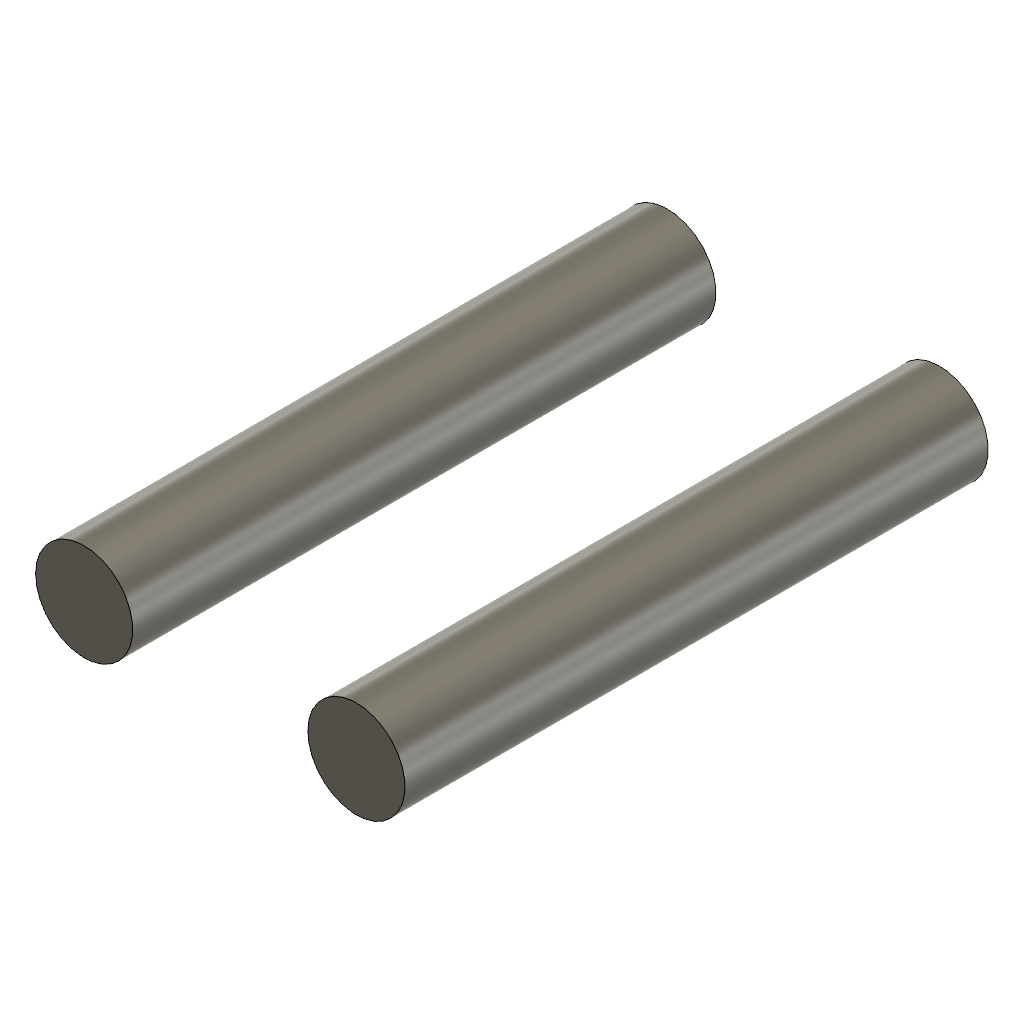
two_profile_collection (Autodesk Fusion 360 design; units mm, degrees)
part number: 2026-10-20-22-24-59-126
Autodesk Fusion 360 part; units mm, degrees
sketch "SweepProfileSection" plane through (0, 0, 0) normal (0, 0, 1) x (1, 0, 0)
  circle A0 centre (-7, 0) radius 2.5
  circle A1 centre (7, 0) radius 2.5
sketch "SweepProfilePath" plane through (0, 0, 0) normal (0, 1, 0) x (1, 0, 0)
  line L0 (0, 0) -> (0, -30)
sweep "ProbeSweepProfile" add profiles "SweepProfileSection" path "SweepProfilePath" along L0 section 1 makes body 1 at (-4.5124, -0.2489, 10) makes body 2 at (9.4876, -0.2489, 10)
